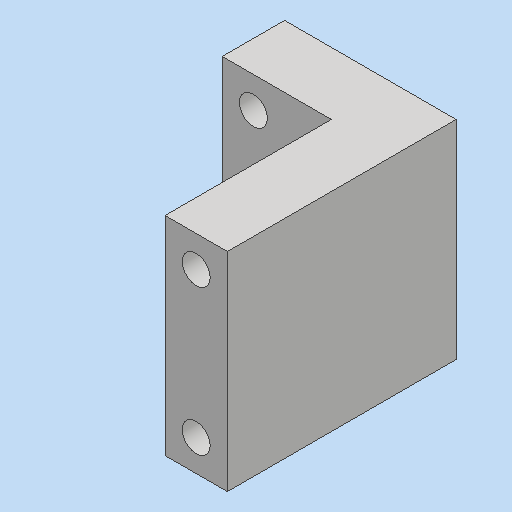
# Autodesk Inventor part: MM0948AN150_G01_102
Saved by Autodesk Inventor 2023.3 (Build 273359000, 359)
## iProperties
Part Number: MM0948AN150_G01_102
Material: 1.2842 90MnCrV8
Description: =<RBPARTNOTITLE2>
Document SubType Name: Modeling
Designer: Benutzer
Mass: 3442.45 g
Surface Area: 600.42 cm^2
Volume: 438.528 cm^3
Density: 7.85 g/cm^3
Appearance: silber AnP
Created: 2023-03-23
RBDOCUMENTTYPE: DRF
RBDOCUMENTVERSION: 00
RBDRAWINGMAINSCALE: 1:1
RBDRAWINGMISSINGSPEC: --
RBDRAWINGVOLUME: --
RBGBEDGESIN1: +0,5
RBGBEDGESIN2: +0,2
RBGBEDGESOUT1: -0,3
RBGBEDGESOUT2: -0,1
RBMATERIAL: =<Material>
RBMATMEETS: --
RBMATNO: =<Part Number>
RBPARTMADEOF: 100 x 110 x 82,5 (FM)
RBPARTNO: SIEHE MNR
RBPARTNOTITLE1: manufactured part
RBPARTNOTITLE2: Anfertigungsteil
RBPARTSAFETYINDICATOR: --
RBSURFACE: chemically nickel-coated
RBSURFACE2: chem. vernickelt
RBZEDGESNORM: ISO13715:2002-06
RBZGENDIMCLASS: m
RBZGENDIMNORM: ISO 2768-1:1989-11
RBZGENGEOCLASS: H
RBZGENGEONORM: ISO 2768-2:1989-11
RBZSURFACENORM: ISO13D2:2002-02
RBZTOLERANCENORM: ISO 14405-1:2010-12
AnP_Material: =<Material>
AnP_TemplVers: 20190222
AnP_Kategorie: 1
MaxAbmaße: 100 x 110 x 82,5 (FM)
AnP_Kommentar_aktuell: =<Comments>
AnP_Material_aktuell: =<Material>
Author: FH/Wi
Keywords: =<RBPARTMADEOF>
Comments: =<RBSURFACE2>
Revision Number: 01
Autodesk Inventor part; units mm, degrees
ref_plane "YZ Plane" through (0, 0, 0) normal (1, 0, 0) x (0, 1, 0)
ref_plane "XZ Plane" through (0, 0, 0) normal (0, 1, 0) x (-1, 0, 0)
ref_plane "XY Plane" through (0, 0, 0) normal (0, 0, 1) x (1, 0, 0)
sketch "Skizze1" plane through (0, 0, 0) normal (0, 0, 1) x (1, 0, 0)
  line L0 (0, 0) -> (0, 80)
  line L1 (0, 80) -> (-52.5, 80)
  line L2 (-52.5, 80) -> (-52.5, 110)
  line L3 (-52.5, 110) -> (30, 110)
  line L4 (30, 110) -> (30, 0)
  line L5 (30, 0) -> (0, 0)
  dimension "d0" = 52.5
  dimension "d1" = 30
  dimension "d2" = 80
  dimension "d3" = 30
  constraints: 12 end point, 5 perpendicular, 1 vertical
  measures "d0" distance of L0.end L1.end
  measures "d1" distance of L1.end L2.end
  measures "d2" distance of L0.start L0.end
  measures "d3" distance between parallel lines of L4 L0
extrude "Extrusion1" add sketch "Skizze1" along normal blind 100
sketch "Skizze2" plane through (-52.5, 110, 0) normal (0, 1, 0) x (1, 0, 0)
  line L0 (0, 0) -> (82.5, 0) projected
  line L1 (0, 0) -> (0, -100) projected
  line L2 (82.5, 0) -> (82.5, -100) projected
  point P0 (52.5, 0)
  point P1 (15, -85)
  point P2 (15, -15)
  point P3 (67.5, -15)
  point P4 (67.5, -85)
  dimension "d6" = 70
  dimension "d7" = 15
  dimension "d8" = 15
  dimension "d16" = 15
  constraints: 2 horizontal alignment, 2 vertical alignment
  measures "d6" distance of point (15, -15) point (15, -85)
  measures "d7" distance from line of point (15, -15) L0
  measures "d8" distance from line of point (15, -15) L1
  measures "d16" distance from line of point (67.5, -15) L2
hole "Bohrung1" at (-37.5, 110, 85) at (-37.5, 110, 15) at (15, 110, 15) at (15, 110, 85) direction (0, -1, 0) diameter 13.5 end through all counterbore diameter 20 counterbore depth 13 clearance for "Inbusschraube ISO 4762  versenkt" size "M12" standard "ISO"
